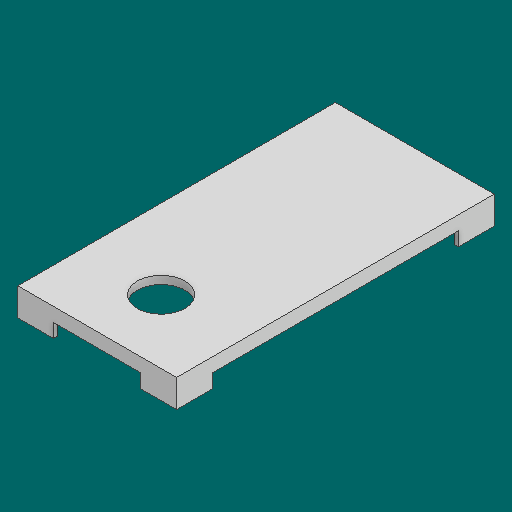
# Autodesk Inventor part: base
Saved by Autodesk Inventor 2027.1 (Build 311270010, 270A)
## iProperties
Created: 2026-11-15
Part Number: base
Material: Generic
Document SubType Name: Modeling
Designer: migue
Density: 1 g/cm^3
Appearance: Default
Author: migue
Autodesk Inventor part; units mm, degrees
ref_plane "YZ Plane" through (0, 0, 0) normal (1, 0, 0) x (0, 1, 0)
ref_plane "XZ Plane" through (0, 0, 0) normal (0, 1, 0) x (-1, 0, 0)
ref_plane "XY Plane" through (0, 0, 0) normal (0, 0, 1) x (1, 0, 0)
sketch "Sketch1" plane through (0, 0, 0) normal (0, 1, 0) x (-1, 0, 0)
  line L0 (0, 0) -> (200, 0)
  line L1 (200, 0) -> (200, -400)
  line L2 (200, -400) -> (0, -400)
  line L3 (0, -400) -> (0, 0)
  dimension "d0" = 200
  dimension "d1" = 400
  constraints: 8 end point, 2 parallel, 1 horizontal, 1 perpendicular
  measures "d0" distance of L1.end L2.end
  measures "d1" distance of L0.end L1.end
extrude "Extrusion1" add sketch "Sketch1" along normal blind 10
sketch "Sketch2" plane through (0, 0, 0) normal (0, -1, 0) x (1, 0, 0)
  line L0 (0, 0) -> (0, -400) projected
  line L1 (-200, 0) -> (0, 0) projected
  line L2 (-200, -400) -> (-200, 0) projected
  line L3 (0, -400) -> (-200, -400) projected
  line L4 (-5, -395) -> (-5, -5)
  line L5 (-5, -5) -> (-195, -5)
  line L6 (-195, -5) -> (-195, -395)
  line L7 (-195, -395) -> (-5, -395)
  dimension "d4" = 5
  constraints: 8 end point, 3 other
  measures "d4" distance between parallel lines of L0 L4
extrude "Extrusion2" add sketch "Sketch2" along normal blind 25
sketch "Sketch3" plane through (0, 10, 0) normal (1, 0, 0) x (0, 0, -1)
  line L0 (0, 0) -> (400, 0) projected
  line L1 (0, -35) -> (0, 0) projected
  line L2 (400, -35) -> (0, -35) projected
  line L3 (400, 0) -> (400, -35) projected
  line L4 (45, -35) -> (355, -35)
  line L5 (355, -35) -> (355, -17.5)
  line L6 (355, -17.5) -> (45, -17.5)
  line L7 (45, -17.5) -> (45, -35)
  point P0 (0, -10)
  dimension "d7" = 45
  dimension "d8" = 45
  dimension "d9" = 17.5
  constraints: 8 end point, 2 parallel, 1 horizontal, 1 perpendicular, 1 point on line
  measures "d7" distance between parallel lines of L1 L7
  measures "d8" distance between parallel lines of L3 L5
  measures "d9" distance between parallel lines of L0 L6
extrude "Extrusion3" cut sketch "Sketch3" against normal through all contours L7 L6 L5 L2
sketch "Sketch4" plane through (0, 10, -400) normal (0, 0, -1) x (-1, 0, 0)
  line L0 (0, 0) -> (200, 0) projected
  line L1 (0, 0) -> (0, -35) projected
  line L2 (200, -35) -> (0, -35) projected
  line L3 (200, -35) -> (200, 0) projected
  line L4 (45, -35) -> (155, -35)
  line L5 (155, -35) -> (155, -17.5)
  line L6 (155, -17.5) -> (45, -17.5)
  line L7 (45, -17.5) -> (45, -35)
  point P0 (0, -10)
  point P1 (45, -26.25)
  point P2 (155, -26.25)
  dimension "d12" = 45
  dimension "d13" = 45
  dimension "d14" = 17.5
  constraints: 8 end point, 2 midpoint, 2 parallel, 1 horizontal, 1 perpendicular, 1 point on line
  measures "d12" distance from line of L1 point (45, -26.25)
  measures "d13" distance from line of L3 point (155, -26.25)
  measures "d14" distance between parallel lines of L0 L6
extrude "Extrusion4" cut sketch "Sketch4" against normal through all contours L7 L6 L5 L2
sketch "Sketch5" plane through (0, 10, 0) normal (0, 1, 0) x (1, 0, 0)
  line L0 (-200, 0) -> (0, 0) projected
  line L1 (0, 0) -> (0, 400) projected
  line L2 (-200, 400) -> (-200, 0) projected
  point P0 (-100, 80.4485)
hole "Hole1" at (-100, 10, -80.4485) direction (0, -1, 0) diameter 60 end through all
body "Solid1"
